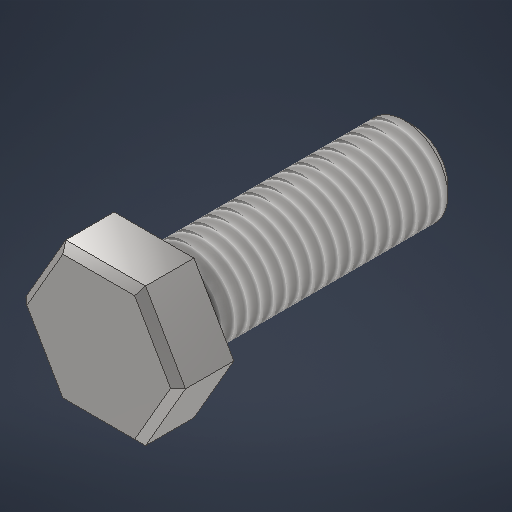
# Autodesk Inventor part: ISO 4017 - M10 x 30
Saved by Autodesk Inventor 2027 (Build 310192000, 192)
## iProperties
Created: 2026-11-07
Part Number: ISO 4017 - M10 x 30
Material: Steel, Carbon
Document SubType Name: Modeling
Designer: Legion
Density: 7.85 g/cm^3
Appearance: Semi-Polished
Description: Hexagon head screw M10 x 30 - 1.5 pitch - class 8.8
Mass: 29.3848 g
Surface Area: 16.9401 cm^2
Volume: 3.74328 cm^3
Strength requirement: ISO 898-1 property class 8.8; design designation, not certified
Material specification: Carbon steel, quenched and tempered to property class 8.8
Compatible wrench: 16 mm nominal across flats
Thread specification: M10 x 1.5 - 6g RH; full thread, 30 mm under head
Author: Legion
Autodesk Inventor part; units mm, degrees
ref_plane "YZ Plane" through (0, 0, 0) normal (1, 0, 0) x (0, 1, 0)
ref_plane "XZ Plane" through (0, 0, 0) normal (0, 1, 0) x (-1, 0, 0)
ref_plane "XY Plane" through (0, 0, 0) normal (0, 0, 1) x (1, 0, 0)
sketch "Hexagon - 16 mm across flats" plane through (0, 0, 0) normal (0, 0, 1) x (1, 0, 0)
  line L0 (9.2376, 0) -> (4.6188, 8)
  line L1 (4.6188, 8) -> (-4.6188, 8)
  line L2 (-4.6188, 8) -> (-9.2376, 0)
  line L3 (-9.2376, 0) -> (-4.6188, -8)
  line L4 (-4.6188, -8) -> (4.6188, -8)
  line L5 (4.6188, -8) -> (9.2376, 0)
  constraints: 12 end point, 2 horizontal, 4 other
extrude "Hex head - 6.4 mm" add sketch "Hexagon - 16 mm across flats" along normal blind 6.4
sketch "M10 blank" plane through (0, 0, 0) normal (0, 0, 1) x (1, 0, 0)
  circle A0 centre (0, 0) radius 5
  constraints: 1 centre point, 1 other
extrude "Bolt length - 30 mm under head" add sketch "M10 blank" against normal blind 30
chamfer "Head edge chamfer" distance 0.8 angle 45 6 edges at (6.9282, -4, 6.4) (0, -8, 6.4) (-6.9282, -4, 6.4) (-6.9282, 4, 6.4) (0, 8, 6.4) (6.9282, 4, 6.4)
chamfer "Thread lead-in - 1 x 45 deg" distance 1 angle 45 1 edges at (-5, 0, -30)
thread "M10 x 1.5 - 6g RH full thread" size "M10x1.5" class "6g" standard "ISO Metric profile" full length
body "Solid1"
